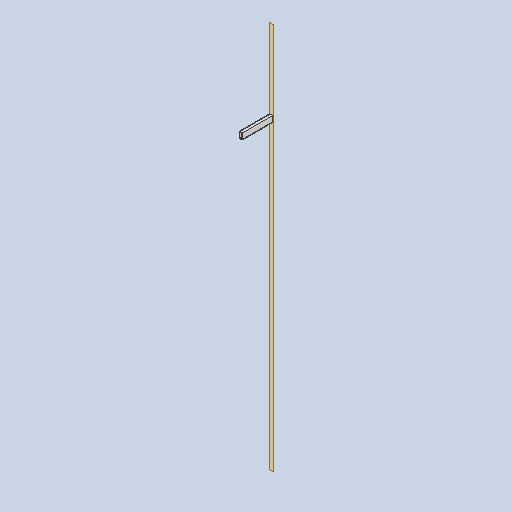
# Autodesk Inventor part: RDS-2005 Tube 40x20 L200
Saved by Autodesk Inventor 2026 (Build 300175000, 175)
## iProperties
Created: 2026-10-26
Part Number: RDS-2005 Tube 40x20 L200
Material: Типовые
Document SubType Name: Modeling
Designer: user
Density: 1 g/cm^3
Appearance: По умолчанию
Author: user
Autodesk Inventor part; units mm, degrees
ref_plane "YZ Plane" through (0, 0, 0) normal (1, 0, 0) x (0, 1, 0)
ref_plane "XZ Plane" through (0, 0, 0) normal (0, 1, 0) x (-1, 0, 0)
ref_plane "XY Plane" through (0, 0, 0) normal (0, 0, 1) x (1, 0, 0)
ref_plane "РабПлоскость1" through (41.803, -1689.278, 513.7984) normal (0, 0, 1) x (1, 0, 0)
sketch "Эскиз1" plane through (41.803, -1689.278, 513.7984) normal (0, 0, 1) x (1, 0, 0)
  line L0 (0, 1900) -> (20, 1900)
  line L1 (20, 1900) -> (20, 1860)
  line L2 (20, 1860) -> (0, 1860)
  line L3 (0, 1860) -> (0, 1900)
  line L4 (0, 2300) -> (20, 2300) projected
  line L5 (2, 1898) -> (18, 1898)
  line L6 (18, 1898) -> (18, 1862)
  line L7 (18, 1862) -> (2, 1862)
  line L8 (2, 1862) -> (2, 1898)
  line L9 (2, 1898) -> (18, 1862) construction
  line L10 (18, 1898) -> (2, 1862) construction
  point P0 (-41.803, 1689.278)
  point P1 (10, 1880)
  dimension "d0" = 20
  dimension "d1" = 40
  dimension "d2" = 400
  dimension "d3" = 20
  dimension "d4" = 16
  dimension "d5" = 36
  dimension "d6" = 2
  dimension "d7" = 2
  constraints: 20 end point, 4 parallel, 2 horizontal, 2 midpoint, 2 perpendicular
  measures "d0" distance of L1.end L2.end
  measures "d1" distance of L0.end L1.end
  measures "d2" distance between parallel lines of L0 L4
  measures "d3" distance from line of L4.start L1
  measures "d4" distance of L6.end L7.end
  measures "d5" distance of L5.end L6.end
  measures "d6" distance between parallel lines of L7 L2
  measures "d7" distance between parallel lines of L8 L3
extrude "Выдавливание1" add sketch "Эскиз1" along normal blind 200
